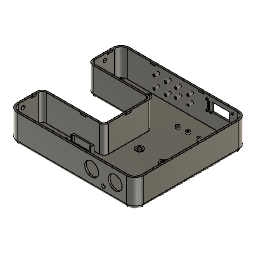
astra-ai-bracket-lid (Autodesk Fusion 360 archive; units mm, degrees)
design "astra-ai-bracket-enclosure_v5"
part number: 2026-04-21-12-29-56-811
Autodesk Fusion 360 part; units mm, degrees
sketch "Sketch1" plane through (0, 0, 0) normal (0, 0, 1) x (1, 0, 0)
  line L0 (0, 50.25) -> (0, 85.25)
  line L1 (15, 100.25) -> (210, 100.25)
  line L2 (0, -50.25) -> (0, -85.25)
  line L3 (15, -100.25) -> (210, -100.25)
  line L4 (225, 85.25) -> (225, -85.25)
  line L5 (10, 40.25) -> (105, 40.25)
  line L6 (10, -40.25) -> (105, -40.25)
  line L7 (110, 35.25) -> (110, -35.25)
  arc A0 (15, 100.25) -> (0, 85.25) centre (15, 85.25) ccw
  arc A1 (225, 85.25) -> (210, 100.25) centre (210, 85.25) ccw
  arc A2 (210, -100.25) -> (225, -85.25) centre (210, -85.25) ccw
  arc A3 (0, -85.25) -> (15, -100.25) centre (15, -85.25) ccw
  arc A4 (10, -40.25) -> (0, -50.25) centre (10, -50.25) ccw
  arc A5 (0, 50.25) -> (10, 40.25) centre (10, 50.25) ccw
  arc A6 (110, 35.25) -> (105, 40.25) centre (105, 35.25) ccw
  arc A7 (105, -40.25) -> (110, -35.25) centre (105, -35.25) ccw
  point P0 (0, 40.25)
  point P1 (0, 100.25)
  point P2 (225, 100.25)
  point P3 (0, -40.25)
  point P4 (0, -100.25)
  point P5 (225, -100.25)
  point P6 (110, 40.25)
  point P7 (110, -40.25)
  dimension "d559" = 60
  dimension "d560" = 225
  dimension "d561" = 60
  dimension "d562" = 40.25
  dimension "d563" = 40.25
  dimension "d564" = 110
  dimension "d565" = 110
  dimension "d873" = 225
  dimension "d955" = 15
  dimension "d956" = 15
  dimension "d957" = 15
  dimension "d958" = 15
  dimension "d959" = 10
  dimension "d960" = 10
  dimension "d961" = 5
  dimension "d962" = 5
  constraint vertical L0
  constraint perpendicular L0 L1
  constraint vertical L2
  constraint perpendicular L2 L3
  constraint perpendicular L0 L5
  constraint perpendicular L0 L6
  constraint perpendicular L6 L7
  constraint coincident P1 L0
  constraint coincident P1 L1
  constraint tangent L0 A0
  constraint tangent L1 A0
  constraint coincident P2 L1
  constraint coincident P2 L4
  constraint tangent L1 A1
  constraint tangent L4 A1
  constraint coincident P5 L3
  constraint coincident P5 L4
  constraint tangent L3 A2
  constraint tangent L4 A2
  constraint coincident P4 L2
  constraint coincident P4 L3
  constraint tangent L2 A3
  constraint tangent L3 A3
  constraint coincident P3 L2
  constraint coincident P3 L6
  constraint tangent L2 A4
  constraint tangent L6 A4
  constraint coincident P0 L0
  constraint coincident P0 L5
  constraint tangent L0 A5
  constraint tangent L5 A5
  constraint coincident P6 L5
  constraint coincident P6 L7
  constraint tangent L5 A6
  constraint tangent L7 A6
  constraint coincident P7 L6
  constraint coincident P7 L7
  constraint tangent L6 A7
  constraint tangent L7 A7
  measures "d559" distance of P0 P1
  measures "d560" distance of P1 P2
  measures "d561" distance of P3 P4
  measures "d562" distance of origin P0
  measures "d563" distance of origin P3
  measures "d564" distance of P0 P6
  measures "d565" distance of P3 P7
  measures "d873" distance of P4 P5
  measures "d955" radius of A0
  measures "d956" radius of A1
  measures "d957" radius of A2
  measures "d958" radius of A3
  measures "d959" radius of A4
  measures "d960" radius of A5
  measures "d961" radius of A6
  measures "d962" radius of A7
extrude "Extrude67" add sketch "Sketch1" along normal blind 3 makes body 1
sketch "Sketch27" plane through (0, 0, 3) normal (0, 0, 1) x (-1, 0, 0)
  line L0 (-10, -40.25) -> (-105, -40.25)
  line L1 (-110, -35.25) -> (-110, 35.25)
  line L2 (-105, 40.25) -> (-10, 40.25)
  line L3 (0, 50.25) -> (0, 85.25)
  line L4 (-15, 100.25) -> (-210, 100.25)
  line L5 (-225, 85.25) -> (-225, -85.25)
  line L6 (-210, -100.25) -> (-15, -100.25)
  line L7 (0, -85.25) -> (0, -50.25)
  arc A0 (-10, 40.25) -> (0, 50.25) centre (-10, 50.25) ccw
  arc A1 (0, 85.25) -> (-15, 100.25) centre (-15, 85.25) ccw
  arc A2 (-210, 100.25) -> (-225, 85.25) centre (-210, 85.25) ccw
  arc A3 (-225, -85.25) -> (-210, -100.25) centre (-210, -85.25) ccw
  arc A4 (-15, -100.25) -> (0, -85.25) centre (-15, -85.25) ccw
  arc A5 (0, -50.25) -> (-10, -40.25) centre (-10, -50.25) ccw
  arc A6 (-110, -35.25) -> (-105, -40.25) centre (-105, -35.25) ccw
  arc A7 (-105, 40.25) -> (-110, 35.25) centre (-105, 35.25) ccw
  line L8 (-10, -43.25) -> (-105, -43.25)
  arc A8 (-113, -35.25) -> (-105, -43.25) centre (-105, -35.25) ccw
  line L9 (-113, -35.25) -> (-113, 35.25)
  arc A9 (-105, 43.25) -> (-113, 35.25) centre (-105, 35.25) ccw
  line L10 (-105, 43.25) -> (-10, 43.25)
  arc A10 (-10, 43.25) -> (-3, 50.25) centre (-10, 50.25) ccw
  line L11 (-3, 50.25) -> (-3, 85.25)
  arc A11 (-3, 85.25) -> (-15, 97.25) centre (-15, 85.25) ccw
  line L12 (-15, 97.25) -> (-210, 97.25)
  arc A12 (-210, 97.25) -> (-222, 85.25) centre (-210, 85.25) ccw
  line L13 (-222, 85.25) -> (-222, -85.25)
  arc A13 (-222, -85.25) -> (-210, -97.25) centre (-210, -85.25) ccw
  line L14 (-210, -97.25) -> (-15, -97.25)
  arc A14 (-15, -97.25) -> (-3, -85.25) centre (-15, -85.25) ccw
  line L15 (-3, -85.25) -> (-3, -50.25)
  arc A15 (-3, -50.25) -> (-10, -43.25) centre (-10, -50.25) ccw
  dimension "d568" = -3
extrude "Extrude68" add sketch "Sketch27" along normal blind 48 bodies 1
sketch "Sketch28" plane through (0, -97.25, 0) normal (0, 1, 0) x (-1, 0, 0)
  line L0 (-210, 3) -> (-15, 3)
  line L1 (-15, 51) -> (-210, 51)
  circle A0 centre (-148, 30) radius 12.375
  circle A1 centre (-190, 30) radius 12.375
  circle A2 centre (-169, 14) radius 3.25
  line L2 (-15, 3) -> (-15, 51)
  line L3 (-210, 51) -> (-210, 3)
  dimension "d571" = 24.75
  dimension "d572" = 24.75
  dimension "d573" = 21
  dimension "d574" = 21
  dimension "d575" = 42
  dimension "d576" = 20
  dimension "d763" = 6.5
  dimension "d764" = 37
  dimension "d883" = 21
  measures "d571" diameter of A0
  measures "d572" diameter of A1
  measures "d573" vertical distance of L1.end A1.centre
  measures "d574" vertical distance of L1.end A0.centre
  measures "d575" distance of A0.centre A1.centre
  measures "d576" horizontal distance of L1.end A1.centre
  measures "d763" diameter of A2
  measures "d764" distance of L1 A2.centre
  measures "d883" horizontal distance of A1.centre A2.centre
extrude "Extrude69" cut sketch "Sketch28" against normal blind 3 contours A0 | A1 | A2 bodies 1
sketch "Sketch29" plane through (0, 0, 3) normal (0, 0, 1) x (-1, 0, 0)
  line L0 (-10, -43.25) -> (-105, -43.25)
  line L1 (-113, -35.25) -> (-113, 35.25)
  line L2 (-105, 43.25) -> (-10, 43.25)
  line L3 (-3, 50.25) -> (-3, 85.25)
  line L4 (-15, 97.25) -> (-210, 97.25)
  line L5 (-222, 85.25) -> (-222, -85.25)
  line L6 (-210, -97.25) -> (-15, -97.25)
  line L7 (-3, -85.25) -> (-3, -50.25)
  circle A0 centre (-12, -88.25) radius 1
  circle A1 centre (-62, -48.25) radius 1
  circle A2 centre (-62, -88.25) radius 3
  circle A3 centre (-12, -48.25) radius 1
  circle A4 centre (-12, -88.25) radius 3
  circle A5 centre (-62, -88.25) radius 1
  circle A6 centre (-12, -48.25) radius 3
  circle A7 centre (-62, -48.25) radius 3
  circle A8 centre (-152, -67.25) radius 1
  circle A9 centre (-152, -67.25) radius 3
  circle A10 centre (-172, -67.25) radius 1
  circle A11 centre (-172, -67.25) radius 3
  circle A12 centre (-134, -67.25) radius 1
  circle A13 centre (-134, -67.25) radius 3
  arc A14 (-10, 43.25) -> (-3, 50.25) centre (-10, 50.25) ccw
  arc A15 (-3, 85.25) -> (-15, 97.25) centre (-15, 85.25) ccw
  arc A16 (-210, 97.25) -> (-222, 85.25) centre (-210, 85.25) ccw
  arc A17 (-222, -85.25) -> (-210, -97.25) centre (-210, -85.25) ccw
  arc A18 (-15, -97.25) -> (-3, -85.25) centre (-15, -85.25) ccw
  arc A19 (-3, -50.25) -> (-10, -43.25) centre (-10, -50.25) ccw
  arc A20 (-113, -35.25) -> (-105, -43.25) centre (-105, -35.25) ccw
  line L8 (-65.9948, 54.3799) -> (-63.9948, 54.3637)
  line L9 (-97.9948, 52.0797) -> (-97.9948, 76.1797)
  arc A21 (-65.9948, 76.1797) -> (-67.4948, 77.6797) centre (-67.4948, 76.1797) ccw
  arc A22 (-96.4948, 77.6797) -> (-97.9948, 76.1797) centre (-96.4948, 76.1797) ccw
  line L10 (-75.9948, 79.6797) -> (-75.9948, 77.6797)
  line L11 (-63.9948, 78.1797) -> (-63.9948, 61.5637)
  line L12 (-100.0003, 54.3797) -> (-100.0003, 47.9797)
  line L13 (-87.9948, 79.6797) -> (-87.9948, 77.6797)
  line L14 (-96.4948, 77.6797) -> (-67.4948, 77.6797)
  arc A23 (-63.9948, 78.1797) -> (-65.4948, 79.6797) centre (-65.4948, 78.1797) ccw
  line L15 (-89.9948, 79.6797) -> (-75.9948, 79.6797)
  line L16 (-98.5003, 79.6797) -> (-87.9948, 79.6797)
  line L17 (-63.9948, 47.9797) -> (-89.9986, 47.9797)
  line L18 (-65.9948, 76.1797) -> (-65.9948, 52.0797)
  line L19 (-65.9948, 61.5637) -> (-63.9948, 61.5637)
  line L20 (-67.4948, 50.5797) -> (-96.4948, 50.5797)
  arc A24 (-98.5003, 79.6797) -> (-100.0003, 78.1797) centre (-98.5003, 78.1797) ccw
  line L21 (-89.9986, 47.9797) -> (-100.0003, 47.9797)
  line L22 (-63.9948, 47.9797) -> (-63.9948, 54.3637)
  line L23 (-97.9948, 54.3797) -> (-100.0003, 54.3797)
  arc A25 (-97.9948, 52.0797) -> (-96.4948, 50.5797) centre (-96.4948, 52.0797) ccw
  arc A26 (-67.4948, 50.5797) -> (-65.9948, 52.0797) centre (-67.4948, 52.0797) ccw
  line L24 (-100.0303, 61.5797) -> (-100.0003, 78.1797)
  line L25 (-65.4948, 79.6797) -> (-89.9948, 79.6797)
  line L26 (-97.9948, 61.5771) -> (-100.0303, 61.5797)
  line L27 (-210, -100.25) -> (-15, -100.25)
  point P0 (0, 40.25)
  point P1 (0, -100.25)
  point P2 (0, -40.25)
  point P3 (-100.0003, 79.6797)
  point P4 (-63.9948, 79.6797)
  point P5 (-65.9948, 50.5797)
  point P6 (-97.9948, 50.5797)
  point P7 (-97.9948, 77.6797)
  point P8 (-65.9948, 77.6797)
  dimension "d579" = 6
  dimension "d580" = 6
  dimension "d581" = 6
  dimension "d582" = 6
  dimension "d587" = 2
  dimension "d588" = 2
  dimension "d589" = 2
  dimension "d590" = 2
  dimension "d811" = 2
  dimension "d812" = 6
  dimension "d813" = 2
  dimension "d814" = 6
  dimension "d815" = 20
  dimension "d818" = 2
  dimension "d819" = 6
  dimension "d867" = 18
  dimension "d963" = 27.1
  dimension "d964" = 32
  dimension "d965" = 3.8
  dimension "d966" = 7.2
  dimension "d971" = 10
  dimension "d972" = 10
  dimension "d975" = 3.8
  dimension "d976" = 7.2
  dimension "d977" = 1.5
  dimension "d978" = 1.5
  dimension "d979" = 1.5
  dimension "d980" = 1.5
  dimension "d981" = 1.5
  dimension "d982" = 1.5
  dimension "d1005" = 12
  dimension "d1006" = 12
  dimension "d1007" = 12
  dimension "d1008" = 12
  dimension "d1009" = 40
  dimension "d1010" = 40
  dimension "d1011" = 50
  dimension "d1012" = 50
  dimension "d1036" = 30
  dimension "d1037" = 50
  constraint concentric A0 A4
  constraint concentric A2 A5
  constraint concentric A3 A6
  constraint concentric A1 A7
  constraint concentric A8 A9
  constraint concentric A10 A11
  constraint concentric A12 A13
  constraint coincident L8.start L18
  constraint perpendicular L17 L22
  constraint perpendicular L21 L22
  constraint perpendicular L11 L20
  constraint coincident L19.start L18
  constraint perpendicular L11 L25
  constraint perpendicular L11 L15
  constraint coincident L10.end L14
  constraint perpendicular L10 L14
  constraint coincident L13.end L14
  constraint perpendicular L13 L14
  constraint coincident L23.start L9
  constraint coincident L26.start L9
  constraint perpendicular L12 L21
  constraint coincident P5 L20
  constraint coincident P5 L18
  constraint tangent L20 A26
  constraint tangent L18 A26
  constraint coincident P8 L14
  constraint coincident P8 L18
  constraint tangent A21 L14
  constraint tangent A21 L18
  constraint coincident P7 L9
  constraint coincident P7 L14
  constraint tangent L9 A22
  constraint tangent A22 L14
  constraint coincident P6 L20
  constraint coincident P6 L9
  constraint tangent L20 A25
  constraint tangent L9 A25
  constraint coincident P4 L11
  constraint coincident P4 L25
  constraint tangent L11 A23
  constraint tangent A23 L25
  constraint coincident P3 L16
  constraint tangent L16 A24
  measures "d579" diameter of A4
  measures "d580" diameter of A2
  measures "d581" diameter of A7
  measures "d582" diameter of A6
  measures "d587" diameter of A0
  measures "d588" diameter of A5
  measures "d589" diameter of A3
  measures "d590" diameter of A1
  measures "d811" diameter of A8
  measures "d812" diameter of A9
  measures "d813" diameter of A10
  measures "d814" diameter of A11
  measures "d815" distance of A8.centre A10.centre
  measures "d818" diameter of A12
  measures "d819" diameter of A13
  measures "d867" distance of A8.centre A12.centre
  measures "d963" distance of P5 P8
  measures "d964" distance of P7 P8
  measures "d965" distance of P5 L8
  measures "d966" distance of L11.end L8.end
  measures "d971" distance of L10.end P8
  measures "d972" distance of L13.end P7
  measures "d975" distance of L23.start P6
  measures "d976" distance of L24.start L12.start
  measures "d977" radius of A26
  measures "d978" radius of A21
  measures "d979" radius of A22
  measures "d980" radius of A25
  measures "d981" radius of A23
  measures "d982" radius of A24
  measures "d1005" horizontal distance of A0.centre P1
  measures "d1006" horizontal distance of A3.centre P1
  measures "d1007" distance of A0.centre L27
  measures "d1008" distance of A2.centre L27
  measures "d1009" distance of A0.centre A3.centre
  measures "d1010" vertical distance of A2.centre A1.centre
  measures "d1011" distance of A0.centre A2.centre
  measures "d1012" distance of A3.centre A1.centre
  measures "d1036" distance of L6 A10.centre
  measures "d1037" distance of L5 A10.centre
sketch "Sketch30" plane through (3, 0, 0) normal (1, 0, 0) x (0, 1, 0)
  line L0 (-85.25, 3) -> (-50.25, 3)
  line L1 (-50.25, 51) -> (-85.25, 51)
  circle A0 centre (-77.25, 41) radius 3.25
  line L2 (-50.25, 3) -> (-50.25, 51)
  line L3 (-85.25, 51) -> (-85.25, 3)
  dimension "d618" = 6.5
  dimension "d619" = 27
  dimension "d620" = 10
  measures "d618" diameter of A0
  measures "d619" horizontal distance of L1.start A0.centre
  measures "d620" vertical distance of L1.start A0.centre
extrude "Extrude70" cut sketch "Sketch30" against normal blind 3 contours A0 bodies 1
sketch "Sketch31" plane through (3, 0, 0) normal (1, 0, 0) x (0, 1, 0)
  line L0 (50.25, 3) -> (85.25, 3)
  line L1 (85.25, 51) -> (50.25, 51)
  circle A0 centre (68.25, 41) radius 3.25
  line L2 (85.25, 3) -> (85.25, 51)
  line L3 (50.25, 51) -> (50.25, 3)
  dimension "d623" = 6.5
  dimension "d624" = 10
  dimension "d625" = 17
  measures "d623" diameter of A0
  measures "d624" vertical distance of L1.start A0.centre
  measures "d625" horizontal distance of L1.start A0.centre
extrude "Extrude71" cut sketch "Sketch31" against normal blind 3 contours A0 bodies 1
sketch "Sketch32" plane through (0, 97.25, 0) normal (0, -1, 0) x (1, 0, 0)
  line L0 (15, 3) -> (210, 3)
  line L1 (210, 51) -> (15, 51)
  circle A0 centre (69.68, 40.4473) radius 2.125
  circle A1 centre (90, 20.1273) radius 2.125
  circle A2 centre (90, 40.4473) radius 2.125
  circle A3 centre (130, 40.4473) radius 2.125
  circle A4 centre (108.41, 25.2073) radius 2.125
  circle A5 centre (90, 40.4473) radius 1
  circle A6 centre (90, 20.1273) radius 1
  circle A7 centre (69.68, 20.1273) radius 2.125
  circle A8 centre (130, 25.2073) radius 2.125
  circle A9 centre (69.68, 20.1273) radius 1
  circle A10 centre (130, 25.2073) radius 1
  circle A11 centre (130, 40.4473) radius 1
  circle A12 centre (69.68, 40.4473) radius 1
  circle A13 centre (108.41, 25.2073) radius 1
  circle A14 centre (108.41, 40.4473) radius 2.125
  circle A15 centre (108.41, 40.4473) radius 1
  line L2 (195.47, 27.415) -> (165.05, 27.415)
  line L3 (156.499, 41.2702) -> (160.499, 41.2702)
  line L4 (195.47, 43.115) -> (195.47, 27.415)
  line L5 (156.499, 36.8152) -> (160.499, 36.8152)
  line L6 (160.499, 38.2702) -> (156.499, 38.2702)
  circle A16 centre (202.4398, 44.155) radius 0.625
  line L7 (156.499, 38.2702) -> (156.499, 41.2702)
  line L8 (160.499, 41.2702) -> (160.499, 38.2702)
  line L9 (156.499, 33.8152) -> (156.499, 36.8152)
  line L10 (160.499, 29.3602) -> (156.499, 29.3602)
  circle A17 centre (156.72, 44.1952) radius 0.625
  circle A18 centre (156.72, 26.4152) radius 0.625
  line L11 (165.05, 27.415) -> (165.05, 43.115)
  circle A19 centre (158.498, 30.83) radius 1.875
  circle A20 centre (161.546, 25.9072) radius 1.875
  line L12 (163.546, 24.4072) -> (159.546, 24.4072)
  line L13 (159.546, 24.4072) -> (159.546, 27.4072)
  circle A21 centre (158.498, 39.71) radius 1.125
  circle A22 centre (158.498, 30.83) radius 1.125
  line L14 (159.546, 27.4072) -> (163.546, 27.4072)
  line L15 (160.499, 33.8152) -> (156.499, 33.8152)
  line L16 (160.499, 36.8152) -> (160.499, 33.8152)
  circle A23 centre (156.72, 44.1952) radius 1.625
  circle A24 centre (202.44, 26.375) radius 0.625
  line L17 (160.499, 32.3602) -> (160.499, 29.3602)
  circle A25 centre (202.4398, 44.155) radius 1.625
  line L18 (165.05, 43.115) -> (195.47, 43.115)
  line L19 (163.546, 27.4072) -> (163.546, 24.4072)
  circle A26 centre (156.72, 26.4152) radius 1.625
  circle A27 centre (158.498, 39.71) radius 1.875
  circle A28 centre (158.498, 35.265) radius 1.875
  circle A29 centre (202.44, 26.375) radius 1.625
  circle A30 centre (158.498, 35.265) radius 1.125
  circle A31 centre (161.546, 25.9072) radius 1.125
  line L20 (156.499, 32.3602) -> (160.499, 32.3602)
  line L21 (156.499, 29.3602) -> (156.499, 32.3602)
  line L22 (210, 3) -> (210, 51)
  line L23 (15, 51) -> (15, 3)
  dimension "d651" = 4.25
  dimension "d652" = 2
  dimension "d655" = 2
  dimension "d656" = 4.25
  dimension "d657" = 2
  dimension "d658" = 4.25
  dimension "d659" = 2
  dimension "d660" = 4.25
  dimension "d661" = 20.32
  dimension "d662" = 20.32
  dimension "d663" = 20.32
  dimension "d664" = 20.32
  dimension "d665" = 2
  dimension "d666" = 4.25
  dimension "d669" = 2
  dimension "d670" = 4.25
  dimension "d671" = 2
  dimension "d672" = 4.25
  dimension "d673" = 2
  dimension "d674" = 4.25
  dimension "d675" = 21.59
  dimension "d676" = 15.24
  dimension "d677" = 15.24
  dimension "d678" = 21.59
  dimension "d759" = 80
  dimension "d761" = 120
  dimension "d762" = 120
  dimension "d894" = 80
  dimension "d895" = 1.25
  dimension "d896" = 1.25
  dimension "d897" = 1.25
  dimension "d898" = 1.25
  dimension "d899" = 3.25
  dimension "d900" = 3.25
  dimension "d901" = 3.25
  dimension "d902" = 3.25
  dimension "d903" = 45.72
  dimension "d904" = 17.78
  dimension "d905" = 17.78
  dimension "d906" = 2.25
  dimension "d907" = 2.25
  dimension "d908" = 2.25
  dimension "d909" = 2.25
  dimension "d913" = 30.42
  dimension "d914" = 15.7
  dimension "d916" = 3.75
  dimension "d917" = 3.75
  dimension "d918" = 3.75
  dimension "d919" = 3.75
  dimension "d926" = 4
  dimension "d927" = 3
  dimension "d929" = 4
  dimension "d930" = 3
  dimension "d932" = 4
  dimension "d933" = 3
  dimension "d934" = 4.455
  dimension "d935" = 4
  dimension "d936" = 3
  dimension "d937" = 4.455
  dimension "d939" = 2.008
  dimension "d941" = 2.945
  constraint concentric A0 A12
  constraint concentric A2 A5
  constraint concentric A7 A9
  constraint concentric A1 A6
  constraint concentric A14 A15
  constraint concentric A3 A11
  constraint concentric A4 A13
  constraint concentric A8 A10
  constraint concentric A24 A29
  constraint concentric A16 A25
  constraint concentric A18 A26
  constraint concentric A17 A23
  constraint concentric A20 A31
  constraint concentric A19 A22
  constraint concentric A28 A30
  constraint concentric A21 A27
  constraint collinear L9 L21
  measures "d651" diameter of A0
  measures "d652" diameter of A12
  measures "d655" diameter of A5
  measures "d656" diameter of A2
  measures "d657" diameter of A9
  measures "d658" diameter of A7
  measures "d659" diameter of A6
  measures "d660" diameter of A1
  measures "d661" distance of A2.centre A0.centre
  measures "d662" vertical distance of A7.centre A0.centre
  measures "d663" vertical distance of A2.centre A1.centre
  measures "d664" distance of A7.centre A1.centre
  measures "d665" diameter of A15
  measures "d666" diameter of A14
  measures "d669" diameter of A11
  measures "d670" diameter of A3
  measures "d671" diameter of A13
  measures "d672" diameter of A4
  measures "d673" diameter of A10
  measures "d674" diameter of A8
  measures "d675" distance of A14.centre A3.centre
  measures "d676" vertical distance of A4.centre A14.centre
  measures "d677" vertical distance of A8.centre A3.centre
  measures "d678" distance of A4.centre A8.centre
  measures "d759" horizontal distance of L1.start A3.centre
  measures "d761" horizontal distance of L1.start A2.centre
  measures "d762" horizontal distance of L0.end A1.centre
  measures "d894" horizontal distance of L0.end A8.centre
  measures "d895" diameter of A24
  measures "d896" diameter of A16
  measures "d897" diameter of A18
  measures "d898" diameter of A17
  measures "d899" diameter of A29
  measures "d900" diameter of A25
  measures "d901" diameter of A26
  measures "d902" diameter of A23
  measures "d903" distance of A24.centre A18.centre
  measures "d904" distance of A16.centre A24.centre
  measures "d905" distance of A17.centre A18.centre
  measures "d906" diameter of A31
  measures "d907" diameter of A22
  measures "d908" diameter of A30
  measures "d909" diameter of A21
  measures "d913" distance of L2.start L2.end
  measures "d914" distance of L2.end L11.end
  measures "d916" diameter of A20
  measures "d917" diameter of A19
  measures "d918" diameter of A28
  measures "d919" diameter of A27
  measures "d926" distance of L12.start L12.end
  measures "d927" distance of L12.end L13.end
  measures "d929" distance of L10.start L10.end
  measures "d930" distance of L10.end L20.start
  measures "d932" distance of L9.start L15.start
  measures "d933" distance of L9.start L5.start
  measures "d934" distance of L10.end L15
  measures "d935" distance of L6.start L6.end
  measures "d936" distance of L6.end L3.start
  measures "d937" distance of L6.end L15
  measures "d939" distance of A18.centre L12
  measures "d941" distance of A18.centre L10
extrude "Extrude74" add sketch "Sketch29" along normal blind 4 contours A2 | A4 | A6 | A7 bodies 1
extrude "Extrude75" add sketch "Sketch32" along normal blind 8 contours A0 | A1 | A2 | A3 | A4 | A7 | A8 | A14 bodies 1
sketch "Sketch33" plane through (0, 0, 3) normal (0, 0, 1) x (-1, 0, 0)
  circle A0 centre (-12, -48.25) radius 3
  circle A1 centre (-12, -88.25) radius 3
  line L0 (-10, -43.25) -> (-105, -43.25)
  line L1 (-105, 43.25) -> (-10, 43.25)
  line L2 (-3, 50.25) -> (-3, 85.25)
  line L3 (-15, 97.25) -> (-210, 97.25)
  line L4 (-222, 85.25) -> (-222, -85.25)
  line L5 (-210, -97.25) -> (-15, -97.25)
  line L6 (-3, -85.25) -> (-3, -50.25)
  circle A2 centre (-62, -88.25) radius 3
  circle A3 centre (-62, -48.25) radius 3
  line L7 (-209, -52.5) -> (-222, -52.5)
  line L8 (-222, -52.5) -> (-222, 52.5)
  line L9 (-222, 52.5) -> (-209, 52.5)
  line L10 (-209, 52.5) -> (-209, -52.5)
  line L11 (-224, 54.5) -> (-207, 54.5)
  line L12 (-207, 54.5) -> (-207, -54.5)
  line L13 (-207, -54.5) -> (-224, -54.5)
  line L14 (-224, -54.5) -> (-224, 54.5)
  arc A4 (-10, 43.25) -> (-3, 50.25) centre (-10, 50.25) ccw
  arc A5 (-3, 85.25) -> (-15, 97.25) centre (-15, 85.25) ccw
  arc A6 (-210, 97.25) -> (-222, 85.25) centre (-210, 85.25) ccw
  arc A7 (-222, -85.25) -> (-210, -97.25) centre (-210, -85.25) ccw
  arc A8 (-15, -97.25) -> (-3, -85.25) centre (-15, -85.25) ccw
  arc A9 (-3, -50.25) -> (-10, -43.25) centre (-10, -50.25) ccw
  arc A10 (-113, -35.25) -> (-105, -43.25) centre (-105, -35.25) ccw
  arc A11 (-105, 43.25) -> (-113, 35.25) centre (-105, 35.25) ccw
  dimension "d871" = 105
  dimension "d872" = 13
  dimension "d874" = 52.5
  dimension "d875" = -2
  constraint horizontal L7
  constraint vertical L8
  constraint horizontal L9
  constraint vertical L10
  constraint coincident L4 L8.end
  measures "d871" distance of L7.start L9.end
  measures "d872" distance of L7.start L7.end
  measures "d874" vertical distance of origin L7.end
extrude "Extrude86" add sketch "Sketch29" along normal blind 3 contours A13 bodies 1
extrude "Extrude87" add sketch "Sketch29" along normal blind 4 contours A9 | A11 bodies 1
sketch "Sketch34" plane through (3, 0, 0) normal (1, 0, 0) x (0, 1, 0)
  circle A0 centre (68.25, 41) radius 3.25
  line L0 (50.25, 3) -> (85.25, 3)
  line L1 (85.25, 51) -> (50.25, 51)
  line L2 (72.25, 51) -> (82.25, 51)
  line L3 (82.25, 51) -> (82.25, 48)
  line L4 (82.25, 48) -> (72.25, 48)
  line L5 (72.25, 48) -> (72.25, 51)
  line L6 (85.25, 3) -> (85.25, 51)
  line L7 (50.25, 51) -> (50.25, 3)
  dimension "d830" = 22
  constraint horizontal L2
  constraint vertical L3
  constraint horizontal L4
  constraint vertical L5
  constraint coincident L1 L2.start
  measures "d830" distance of L1.end L2.start
extrude "Extrude88" add sketch "Sketch34" along normal blind 3 draft -45 contours L1 L2 L3 L4 L5 bodies 1
sketch "Sketch35" plane through (3, 0, 0) normal (1, 0, 0) x (0, 1, 0)
  circle A0 centre (-77.25, 41) radius 3.25
  line L0 (-85.25, 3) -> (-50.25, 3)
  line L1 (-50.25, 51) -> (-85.25, 51)
  line L2 (-63.25, 51) -> (-53.25, 51)
  line L3 (-53.25, 51) -> (-53.25, 48)
  line L4 (-53.25, 48) -> (-63.25, 48)
  line L5 (-63.25, 48) -> (-63.25, 51)
  line L6 (-50.25, 3) -> (-50.25, 51)
  line L7 (-85.25, 51) -> (-85.25, 3)
  dimension "d827" = 22
  constraint horizontal L2
  constraint vertical L3
  constraint horizontal L4
  constraint vertical L5
  constraint coincident L1 L2.start
  measures "d827" distance of L1.end L2.start
extrude "Extrude89" add sketch "Sketch35" along normal blind 3 draft -45 separate body contours L1 L2 L3 L4 L5 makes body 2
sketch "Sketch36" plane through (113, 0, 0) normal (1, 0, 0) x (0, 1, 0)
  line L0 (-35.25, 3) -> (35.25, 3)
  line L1 (35.25, 51) -> (-35.25, 51)
  line L2 (5, 51) -> (-5, 51)
  line L3 (-5, 51) -> (-5, 48)
  line L4 (-5, 48) -> (5, 48)
  line L5 (5, 48) -> (5, 51)
  line L6 (35.25, 3) -> (35.25, 51)
  line L7 (-35.25, 51) -> (-35.25, 3)
  constraint horizontal L2
  constraint vertical L3
  constraint horizontal L4
  constraint vertical L5
  constraint coincident L1 L2.start
extrude "Extrude90" add sketch "Sketch36" along normal blind 3 draft -45 separate body contours L1 L2 L3 L4 L5 makes body 3
sketch "Sketch37" plane through (0, -43.25, 0) normal (0, -1, 0) x (1, 0, 0)
  line L0 (10, 3) -> (105, 3)
  line L1 (105, 51) -> (10, 51)
  line L2 (71, 51) -> (81, 51)
  line L3 (81, 51) -> (81, 48)
  line L4 (81, 48) -> (71, 48)
  line L5 (71, 48) -> (71, 51)
  line L6 (105, 3) -> (105, 51)
  line L7 (10, 51) -> (10, 3)
  dimension "d833" = 61
  constraint horizontal L2
  constraint vertical L3
  constraint horizontal L4
  constraint vertical L5
  constraint coincident L1 L2.start
  measures "d833" distance of L1.end L2.start
extrude "Extrude91" add sketch "Sketch37" along normal blind 3 draft -45 separate body contours L1 L2 L3 L4 L5 makes body 4
sketch "Sketch38" plane through (0, 43.25, 0) normal (0, 1, 0) x (-1, 0, 0)
  line L0 (-105, 3) -> (-10, 3)
  line L1 (-10, 51) -> (-105, 51)
  line L2 (-81, 51) -> (-71, 51)
  line L3 (-71, 51) -> (-71, 48)
  line L4 (-71, 48) -> (-81, 48)
  line L5 (-81, 48) -> (-81, 51)
  line L6 (-10, 3) -> (-10, 51)
  line L7 (-105, 51) -> (-105, 3)
  dimension "d836" = 61
  dimension "d953" = 10
  dimension "d954" = 3
  constraint horizontal L2
  constraint vertical L3
  constraint horizontal L4
  constraint vertical L5
  constraint coincident L1 L2.start
  measures "d836" distance of L1.start L2.end
  measures "d953" distance of L2.start L2.end
  measures "d954" distance of L2.start L4.end
extrude "Extrude92" add sketch "Sketch38" along normal blind 3 draft -45 separate body contours L1 L2 L3 L4 L5 makes body 5
sketch "Sketch39" plane through (0, 97.25, 0) normal (0, -1, 0) x (1, 0, 0)
  circle A0 centre (130, 25.2073) radius 2.125
  circle A1 centre (69.68, 20.1273) radius 2.125
  circle A2 centre (130, 40.4473) radius 2.125
  circle A3 centre (69.68, 40.4473) radius 2.125
  line L0 (15, 3) -> (210, 3)
  line L1 (210, 51) -> (15, 51)
  circle A4 centre (108.41, 25.2073) radius 2.125
  circle A5 centre (90, 40.4473) radius 2.125
  circle A6 centre (108.41, 40.4473) radius 2.125
  circle A7 centre (90, 20.1273) radius 2.125
  line L2 (55, 51) -> (65, 51)
  line L3 (65, 51) -> (65, 48)
  line L4 (65, 48) -> (55, 48)
  line L5 (55, 48) -> (55, 51)
  line L6 (140, 51) -> (150, 51)
  line L7 (150, 51) -> (150, 48)
  line L8 (150, 48) -> (140, 48)
  line L9 (140, 48) -> (140, 51)
  line L10 (210, 3) -> (210, 51)
  line L11 (15, 51) -> (15, 3)
  dimension "d839" = 40
  dimension "d840" = 60
  dimension "d890" = 10
  dimension "d891" = 10
  dimension "d892" = 3
  dimension "d893" = 3
  constraint horizontal L2
  constraint vertical L3
  constraint horizontal L4
  constraint vertical L5
  constraint coincident L1 L2.start
  constraint horizontal L6
  constraint vertical L7
  constraint horizontal L8
  constraint vertical L9
  constraint coincident L1 L6.start
  measures "d839" distance of L1.end L2.start
  measures "d840" distance of L1.start L6.end
  measures "d890" distance of L2.start L2.end
  measures "d891" distance of L6.start L6.end
  measures "d892" distance of L2.end L3.end
  measures "d893" distance of L6.start L8.end
extrude "Extrude93" add sketch "Sketch39" along normal blind 3 draft -45 separate body contours L1 L2 L3 L4 L5 | L1 L6 L7 L8 L9 makes body 6 at (143.3333, 97.25, 50) makes body 7 at (58.3333, 97.25, 49)
sketch "Sketch40" plane through (0, -97.25, 0) normal (0, 1, 0) x (-1, 0, 0)
  circle A0 centre (-190, 30) radius 12.375
  circle A1 centre (-148, 30) radius 12.375
  circle A2 centre (-169, 14) radius 3.25
  line L0 (-210, 3) -> (-15, 3)
  line L1 (-15, 51) -> (-210, 51)
  line L2 (-65, 51) -> (-75, 51)
  line L3 (-75, 51) -> (-75, 48)
  line L4 (-75, 48) -> (-65, 48)
  line L5 (-65, 48) -> (-65, 51)
  line L6 (-163, 51) -> (-173, 51)
  line L7 (-173, 51) -> (-173, 48)
  line L8 (-173, 48) -> (-163, 48)
  line L9 (-163, 48) -> (-163, 51)
  line L10 (-15, 3) -> (-15, 51)
  line L11 (-210, 51) -> (-210, 3)
  dimension "d843" = 60
  dimension "d844" = 47
  dimension "d880" = 3
  dimension "d881" = 3
  dimension "d1015" = 10
  dimension "d1016" = 10
  constraint horizontal L2
  constraint vertical L3
  constraint horizontal L4
  constraint vertical L5
  constraint coincident L1 L2.start
  constraint horizontal L6
  constraint vertical L7
  constraint horizontal L8
  constraint vertical L9
  constraint coincident L1 L6.start
  measures "d843" distance of L1.start L2.end
  measures "d844" distance of L1.end L6.start
  measures "d880" distance of L6.start L8.end
  measures "d881" distance of L2.start L4.end
  measures "d1015" distance of L6.start L6.end
  measures "d1016" distance of L2.start L2.end
extrude "Extrude94" add sketch "Sketch40" along normal blind 3 draft -45 separate body contours L1 L6 L7 L8 L9 | L1 L2 L3 L4 L5 makes body 8 at (169.6667, -97.25, 50) makes body 9 at (68.3333, -97.25, 49)
sketch "Sketch41" plane through (222, 0, 0) normal (-1, 0, 0) x (0, -1, 0)
  line L0 (-85.25, 3) -> (85.25, 3)
  line L1 (85.25, 51) -> (-85.25, 51)
  line L2 (-65.25, 51) -> (-55.25, 51)
  line L3 (-55.25, 51) -> (-55.25, 48)
  line L4 (-55.25, 48) -> (-65.25, 48)
  line L5 (-65.25, 48) -> (-65.25, 51)
  line L6 (65.25, 51) -> (55.25, 51)
  line L7 (55.25, 51) -> (55.25, 48)
  line L8 (55.25, 48) -> (65.25, 48)
  line L9 (65.25, 48) -> (65.25, 51)
  line L10 (85.25, 3) -> (85.25, 51)
  line L11 (-85.25, 51) -> (-85.25, 3)
  dimension "d847" = 20
  dimension "d848" = 20
  dimension "d886" = 3
  dimension "d887" = 3
  dimension "d888" = 10
  dimension "d889" = 10
  constraint horizontal L2
  constraint vertical L3
  constraint horizontal L4
  constraint vertical L5
  constraint coincident L1 L2.start
  constraint horizontal L6
  constraint vertical L7
  constraint horizontal L8
  constraint vertical L9
  constraint coincident L1 L6.start
  measures "d847" distance of L1.end L2.start
  measures "d848" distance of L1.start L6.start
  measures "d886" distance of L2.end L3.end
  measures "d887" distance of L6.start L8.end
  measures "d888" distance of L2.start L2.end
  measures "d889" distance of L6.start L6.end
extrude "Extrude95" add sketch "Sketch41" along normal blind 3 draft -45 separate body contours L1 L2 L3 L4 L5 | L1 L6 L7 L8 L9 makes body 10 at (222, -58.5833, 50) makes body 11 at (222, 61.9167, 50)
extrude "Extrude100" cut sketch "Sketch33" against normal blind 1 contours L4 L7 L8 L9 L10 bodies 1
extrude "Extrude101" add sketch "Sketch33" along normal blind 11 contours L4 L7 L9 L10 L11 L12 L13 bodies 1
extrude "Extrude103" cut sketch "Sketch32" against normal blind 4 contours L2 L4 L11 L18 bodies 1
extrude "Extrude104" add sketch "Sketch32" along normal blind 1.5 contours A23 | A25 | A26 | A29 bodies 1
extrude "Extrude105" cut sketch "Sketch32" against normal blind 3.25 contours A21 | A22 | A30 | A31 bodies 1
extrude "Extrude106" cut sketch "Sketch32" against normal blind 1.5 contours L3 L6 L7 A27 | L3 A27 | L3 L6 A27 | L3 L6 L8 A27 | L6 A27 | L5 L9 L15 A28 | L5 A28 | L5 L15 A28 | L5 L15 L16 A28 | L15 A28 | L10 A19 L17 L20 | L10 A19 | L10 A19 L20 | L10 A19 L20 L21 | A19 L20 | A20 L12 L14 | A20 L12 L14 L19 | A20 L14 | A20 L12 | A20 L12 L13 L14 bodies 1
extrude "Extrude107" add sketch "Sketch29" along normal blind 3 contours L9 A21 A22 L14 L18 L20 A25 A26 bodies 1
extrude "Extrude108" add sketch "Sketch29" along normal blind 14 contours L8 L9 L12 L17 L18 L20 L21 L22 L23 A25 A26 | A21 L10 L11 L14 A23 L18 L19 L25 | L9 A22 L13 L14 L15 L16 A24 L24 L25 L26 bodies 1
sketch "Sketch46" plane through (0, -50.5797, 0) normal (0, -1, 0) x (1, 0, 0)
  line L0 (67.4948, 6) -> (96.4948, 6)
  line L1 (96.4948, 6) -> (96.4948, 17)
  line L2 (96.4948, 17) -> (67.4948, 17)
  line L3 (67.4948, 17) -> (67.4948, 6)
  line L4 (70.4948, 17) -> (74.4948, 17)
  line L5 (74.4948, 17) -> (74.4948, 15)
  line L6 (74.4948, 15) -> (70.4948, 15)
  line L7 (70.4948, 15) -> (70.4948, 17)
  line L8 (93.4948, 17) -> (89.4948, 17)
  line L9 (89.4948, 17) -> (89.4948, 15)
  line L10 (89.4948, 15) -> (93.4948, 15)
  line L11 (93.4948, 15) -> (93.4948, 17)
  dimension "d987" = 4
  dimension "d988" = 2
  dimension "d989" = 4
  dimension "d990" = 2
  dimension "d991" = 3
  dimension "d992" = 3
  constraint horizontal L4
  constraint vertical L5
  constraint horizontal L6
  constraint vertical L7
  constraint coincident L2 L4.start
  constraint horizontal L8
  constraint vertical L9
  constraint horizontal L10
  constraint vertical L11
  constraint coincident L2 L8.start
  measures "d987" distance of L8.start L8.end
  measures "d988" distance of L8.end L9.end
  measures "d989" distance of L4.start L4.end
  measures "d990" distance of L4.end L5.end
  measures "d991" distance of L1.end L8.start
  measures "d992" distance of L2.end L4.start
extrude "Extrude109" add sketch "Sketch46" along normal blind 2 draft -45 separate body contours L2 L4 L5 L6 L7 | L2 L8 L9 L10 L11 makes body 12 at (71.8281, -50.5797, 16.3333) makes body 13 at (90.8281, -50.5797, 16.3333)
sketch "Sketch47" plane through (65.9948, 0, 0) normal (1, 0, 0) x (0, 1, 0)
  line L0 (-76.1797, 6) -> (-61.5637, 6)
  line L1 (-61.5637, 6) -> (-61.5637, 17)
  line L2 (-61.5637, 17) -> (-76.1797, 17)
  line L3 (-76.1797, 17) -> (-76.1797, 6)
  line L4 (-71.1797, 17) -> (-67.1797, 17)
  line L5 (-67.1797, 17) -> (-67.1797, 15)
  line L6 (-67.1797, 15) -> (-71.1797, 15)
  line L7 (-71.1797, 15) -> (-71.1797, 17)
  dimension "d995" = 4
  dimension "d996" = 2
  dimension "d997" = 5
  constraint horizontal L4
  constraint vertical L5
  constraint horizontal L6
  constraint vertical L7
  constraint coincident L2 L4.start
  measures "d995" distance of L4.start L4.end
  measures "d996" distance of L4.end L5.end
  measures "d997" distance of L2.end L4.start
extrude "Extrude110" add sketch "Sketch47" along normal blind 2 draft -45 separate body contours L2 L4 L5 L6 L7 makes body 14
sketch "Sketch48" plane through (0, -77.6797, 0) normal (0, 1, 0) x (-1, 0, 0)
  line L0 (-96.4948, 6) -> (-87.9948, 6)
  line L1 (-87.9948, 6) -> (-87.9948, 17)
  line L2 (-87.9948, 17) -> (-96.4948, 17)
  line L3 (-96.4948, 17) -> (-96.4948, 6)
  line L4 (-94.4948, 17) -> (-90.4948, 17)
  line L5 (-90.4948, 17) -> (-90.4948, 15)
  line L6 (-90.4948, 15) -> (-94.4948, 15)
  line L7 (-94.4948, 15) -> (-94.4948, 17)
  dimension "d1000" = 4
  dimension "d1001" = 2
  dimension "d1002" = 2
  constraint horizontal L4
  constraint vertical L5
  constraint horizontal L6
  constraint vertical L7
  constraint coincident L2 L4.start
  measures "d1000" distance of L4.start L4.end
  measures "d1001" distance of L4.end L5.end
  measures "d1002" distance of L2.end L4.start
extrude "Extrude111" add sketch "Sketch48" along normal blind 2 draft -45 separate body contours L2 L4 L5 L6 L7 makes body 15
fillet "Fillet1" radius 7 16 edges at (225, 0, 0) (220.6066, 95.8566, 0) (112.5, 100.25, 0) (4.3934, 95.8566, 0) (0, 67.75, 0) (2.9289, 43.1789, 0) (57.5, 40.25, 0) (108.5355, 38.7855, 0) (110, 0, 0) (108.5355, -38.7855, 0) (57.5, -40.25, 0) (2.9289, -43.1789, 0) (0, -67.75, 0) (4.3934, -95.8566, 0) (112.5, -100.25, 0) (220.6066, -95.8566, 0) on bodies 1
extrude "Extrude112" cut sketch "Sketch32" against normal blind 2.25 contours L3 A27 | L3 L6 A27 | L6 A27 | L5 A28 | L5 L15 A28 | L15 A28 | L10 A19 | L10 A19 L20 | A19 L20 | A20 L12 L14 | A20 L14 | A20 L12 bodies 1
sketch "Sketch49" plane through (0, 0, 3) normal (0, 0, 1) x (-1, 0, 0)
  line L0 (-97.9948, 61.5771) -> (-100.0303, 61.5797)
  line L1 (-100.0303, 61.5797) -> (-100.0003, 78.1797)
  arc A0 (-98.5003, 79.6797) -> (-100.0003, 78.1797) centre (-98.5003, 78.1797) ccw
  line L2 (-98.5003, 79.6797) -> (-87.9948, 79.6797)
  line L3 (-87.9948, 79.6797) -> (-87.9948, 77.6797)
  line L4 (-87.9948, 77.6797) -> (-75.9948, 77.6797)
  line L5 (-75.9948, 77.6797) -> (-75.9948, 79.6797)
  line L6 (-75.9948, 79.6797) -> (-65.4948, 79.6797)
  arc A1 (-63.9948, 78.1797) -> (-65.4948, 79.6797) centre (-65.4948, 78.1797) ccw
  line L7 (-63.9948, 78.1797) -> (-63.9948, 61.5637)
  line L8 (-63.9948, 61.5637) -> (-65.9948, 61.5637)
  line L9 (-65.9948, 61.5637) -> (-65.9948, 54.3799)
  line L10 (-65.9948, 54.3799) -> (-63.9948, 54.3637)
  line L11 (-63.9948, 54.3637) -> (-63.9948, 47.9797)
  line L12 (-63.9948, 47.9797) -> (-100.0003, 47.9797)
  line L13 (-100.0003, 47.9797) -> (-100.0003, 54.3797)
  line L14 (-100.0003, 54.3797) -> (-97.9948, 54.3797)
  line L15 (-97.9948, 54.3797) -> (-97.9948, 61.5771)
  line L16 (-207, -54.5) -> (-222, -54.5)
  line L17 (-222, -54.5) -> (-222, -85.25)
  arc A2 (-222, -85.25) -> (-210, -97.25) centre (-210, -85.25) ccw
  line L18 (-210, -97.25) -> (-15, -97.25)
  arc A3 (-15, -97.25) -> (-3, -85.25) centre (-15, -85.25) ccw
  line L19 (-3, -85.25) -> (-3, -50.25)
  arc A4 (-3, -50.25) -> (-10, -43.25) centre (-10, -50.25) ccw
  line L20 (-10, -43.25) -> (-105, -43.25)
  arc A5 (-113, -35.25) -> (-105, -43.25) centre (-105, -35.25) ccw
  line L21 (-113, -35.25) -> (-113, 35.25)
  arc A6 (-105, 43.25) -> (-113, 35.25) centre (-105, 35.25) ccw
  line L22 (-105, 43.25) -> (-10, 43.25)
  arc A7 (-10, 43.25) -> (-3, 50.25) centre (-10, 50.25) ccw
  line L23 (-3, 50.25) -> (-3, 85.25)
  arc A8 (-3, 85.25) -> (-15, 97.25) centre (-15, 85.25) ccw
  line L24 (-15, 97.25) -> (-210, 97.25)
  arc A9 (-210, 97.25) -> (-222, 85.25) centre (-210, 85.25) ccw
  line L25 (-222, 85.25) -> (-222, 54.5)
  line L26 (-222, 54.5) -> (-207, 54.5)
  line L27 (-207, 54.5) -> (-207, -54.5)
  circle A10 centre (-152, -67.25) radius 3
  circle A11 centre (-134, -67.25) radius 3
  circle A12 centre (-12, -48.25) radius 3
  circle A13 centre (-12, -88.25) radius 3
  circle A14 centre (-62, -88.25) radius 3
  circle A15 centre (-62, -48.25) radius 3
  circle A16 centre (-172, -67.25) radius 3
  circle A17 centre (-175, -0.2325) radius 6.125
  circle A18 centre (-175, -0.2325) radius 3.375
  circle A19 centre (-195, 10) radius 3.375
  circle A20 centre (-195, 10) radius 6.125
  circle A21 centre (-195, -10) radius 3.375
  circle A22 centre (-195, -10) radius 6.125
  circle A23 centre (-133, 0) radius 3.375
  circle A24 centre (-133, 0) radius 6.125
  dimension "d1019" = 6.75
  dimension "d1020" = 12.25
  dimension "d1021" = 6.75
  dimension "d1022" = 12.25
  dimension "d1023" = 20
  dimension "d1024" = 6.75
  dimension "d1025" = 12.25
  dimension "d1026" = 20
  dimension "d1027" = 87.25
  dimension "d1028" = 195
  dimension "d1033" = 6.75
  dimension "d1034" = 12.25
  dimension "d1035" = 42
  constraint concentric A19 A20
  constraint concentric A21 A22
  constraint concentric A17 A18
  constraint concentric A23 A24
  measures "d1019" diameter of A19
  measures "d1020" diameter of A20
  measures "d1021" diameter of A21
  measures "d1022" diameter of A22
  measures "d1023" distance of A19.centre A21.centre
  measures "d1024" diameter of A18
  measures "d1025" diameter of A17
  measures "d1026" horizontal distance of A19.centre A17.centre
  measures "d1027" distance of L24 A19.centre
  measures "d1028" horizontal distance of origin A19.centre
  measures "d1033" diameter of A23
  measures "d1034" diameter of A24
  measures "d1035" horizontal distance of A17.centre A23.centre
extrude "Extrude113" cut sketch "Sketch49" against normal blind 5 contours A18 | A19 | A21 | A23 bodies 1
extrude "Extrude114" add sketch "Sketch49" along normal blind 1.25 separate body contours A17 | A20 | A22 | A24 makes body 16 at (198.5943, 13.7501, 3) makes body 17 at (198.5943, -6.2499, 3) makes body 18 at (178.5943, 3.9826, 3) makes body 19 at (131.5494, -4.9878, 3)
